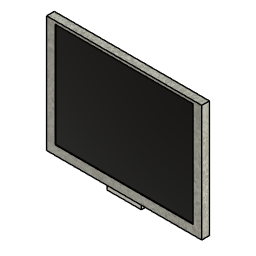
GNS 530 CAD v100 (Autodesk Fusion 360 archive; units mm, degrees)
design "GNS 530 5 inch Screen"
Autodesk Fusion 360 part; units mm, degrees
sketch "Sketch1" plane through (0, 0, 0) normal (0, 1, 0) x (1, 0, 0)
  line L0 (58.82, -44.225) -> (-58.82, -44.225)
  line L1 (-58.82, -44.225) -> (-58.82, 44.225)
  line L2 (-58.82, 44.225) -> (58.82, 44.225)
  line L3 (58.82, 44.225) -> (58.82, -44.225)
  line L4 (58.82, -44.225) -> (-58.82, 44.225) construction
  line L5 (-58.82, -44.225) -> (58.82, 44.225) construction
  line L6 (52.32, -41.925) -> (-52.32, -41.925)
  line L7 (-52.32, -41.925) -> (-52.32, 37.225)
  line L8 (-52.32, 37.225) -> (52.32, 37.225)
  line L9 (52.32, 37.225) -> (52.32, -41.925)
  line L10 (52.32, -41.925) -> (-52.32, 37.225) construction
  line L11 (-52.32, -41.925) -> (52.32, 37.225) construction
  point P0 (0, -2.35)
  dimension "d1" = 117.64
  dimension "d2" = 88.45
  dimension "d5" = 6.5
  dimension "d6" = 6.5
  dimension "d7" = 2.3
  dimension "d8" = 7
  constraint horizontal L0
  constraint perpendicular L0 L1
  constraint parallel L0 L2
  constraint parallel L1 L3
  constraint coincident L4 origin
  constraint coincident L5 origin
  constraint horizontal L6
  constraint perpendicular L6 L7
  constraint parallel L6 L8
  constraint parallel L7 L9
  constraint coincident L10 P0
  constraint coincident L11 P0
  measures "d1" distance of L1.end L2.end
  measures "d2" distance of L0.end L1.end
  measures "d5" distance of L3 L9
  measures "d6" distance of L1 L7
  measures "d7" distance of L0 L6
  measures "d8" distance of L2 L8
extrude "Extrude1" add sketch "Sketch1" along normal blind 5.85 contours L0 L1 L2 L3 | L6 L7 L8 L9 makes body 1
extrude "Extrude2" cut sketch "Sketch1" along normal blind 0.5 contours L6 L7 L8 L9 bodies 1
sketch "Sketch2" plane through (0, 0, -44.225) normal (0, 0, -1) x (1, 0, 0)
  line L0 (58.82, 0) -> (-58.82, 0)
  line L1 (-58.82, 0) -> (-58.82, -5.85)
  line L2 (-58.82, -5.85) -> (58.82, -5.85)
  line L3 (58.82, -5.85) -> (58.82, 0)
  line L4 (13, -5.85) -> (-13, -5.85)
  line L5 (-13, -5.85) -> (-13, 5.85)
  line L6 (-13, 5.85) -> (13, 5.85)
  line L7 (13, 5.85) -> (13, -5.85)
  line L8 (13, -5.85) -> (-13, 5.85) construction
  line L9 (-13, -5.85) -> (13, 5.85) construction
  dimension "d11" = 26
  constraint horizontal L4
  constraint perpendicular L4 L5
  constraint parallel L4 L6
  constraint parallel L5 L7
  constraint coincident L8 origin
  constraint coincident L9 origin
  measures "d11" distance of L5.end L6.end
extrude "Extrude3" add sketch "Sketch2" along normal blind 3 separate body contours L0 L2 L4 L5 L7 makes body 2
sketch "Sketch3" plane through (0, 5.85, 0) normal (0, 1, 0) x (-1, 0, 0)
  line L0 (-58.82, -44.225) -> (58.82, -44.225)
  line L1 (58.82, -44.225) -> (58.82, 44.225)
  line L2 (58.82, 44.225) -> (-58.82, 44.225)
  line L3 (-58.82, 44.225) -> (-58.82, -44.225)
  line L4 (57.94, 35.525) -> (55.29, 35.525)
  line L5 (55.29, 35.525) -> (55.29, 32.085)
  line L6 (55.29, 32.085) -> (57.94, 32.085)
  line L7 (57.94, 32.085) -> (57.94, 35.525)
  line L8 (55.29, -28.425) -> (57.94, -28.425)
  line L9 (57.94, -28.425) -> (57.94, -31.865)
  line L10 (57.94, -31.865) -> (55.29, -31.865)
  line L11 (55.29, -31.865) -> (55.29, -28.425)
  line L12 (-57.74, 35.525) -> (-52.39, 35.525)
  line L13 (-52.39, 35.525) -> (-52.39, 31.985)
  line L14 (-52.39, 31.985) -> (-57.74, 31.985)
  line L15 (-57.74, 31.985) -> (-57.74, 35.525)
  line L16 (-57.74, -31.865) -> (-52.39, -31.865)
  line L17 (-52.39, -31.865) -> (-52.39, -28.325)
  line L18 (-52.39, -28.325) -> (-57.74, -28.325)
  line L19 (-57.74, -28.325) -> (-57.74, -31.865)
  dimension "d14" = 0.88
  dimension "d15" = 2.65
  dimension "d16" = 3.44
  dimension "d17" = 8.7
  dimension "d18" = 12.36
  dimension "d19" = 5.35
  dimension "d20" = 3.54
  dimension "d22" = 1.08
  constraint horizontal L4
  constraint vertical L5
  constraint horizontal L6
  constraint vertical L7
  constraint horizontal L8
  constraint vertical L9
  constraint horizontal L10
  constraint vertical L11
  constraint equal L7 L9
  constraint equal L6 L8
  constraint collinear L7 L9
  constraint horizontal L12
  constraint vertical L13
  constraint horizontal L14
  constraint vertical L15
  constraint collinear L4 L12
  constraint horizontal L16
  constraint vertical L17
  constraint horizontal L18
  constraint vertical L19
  constraint equal L12 L18
  constraint equal L13 L17
  constraint collinear L15 L19
  constraint collinear L10 L16
  measures "d14" distance of L1 L7
  measures "d15" distance of L4.start L4.end
  measures "d16" distance of L4.end L5.end
  measures "d17" distance of L2 L4
  measures "d18" distance of L0 L10
  measures "d19" distance of L12.start L12.end
  measures "d20" distance of L12.start L14.end
  measures "d22" distance of L3 L15
extrude "Extrude4" cut sketch "Sketch3" against normal blind 3.7 contours L4 L5 L6 L7 | L8 L9 L10 L11 | L12 L13 L14 L15 | L16 L17 L18 L19 bodies 1

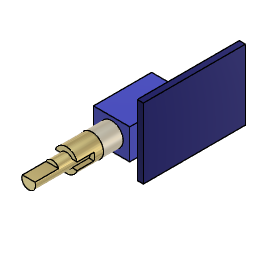
design "PropWashSim Dual Encoder (6mm screw, 6.5 loose)"
Autodesk Fusion 360 part; units mm, degrees
sketch "Profile" plane through (0, 0, 0) normal (0, 1, 0) x (1, 0, 0)
  line L0 (4.6, 3.85) -> (-4.6, 3.85)
  line L1 (-4.6, 3.85) -> (-4.6, -3.85)
  line L2 (-4.6, -3.85) -> (4.6, -3.85)
  line L3 (4.6, -3.85) -> (4.6, 3.85)
  line L4 (4.6, 3.85) -> (-4.6, -3.85) construction
  line L5 (-4.6, 3.85) -> (4.6, -3.85) construction
  circle A0 centre (0, 0) radius 2.925
  line L6 (2.235, -1.8869) -> (2.235, 1.8869)
  line L7 (0, 0) -> (0, 6.159) construction
  line L8 (-2.235, -1.8869) -> (-2.235, 1.8869)
  line L9 (-2.7664, -0.95) -> (2.7664, -0.95)
  line L10 (0, 0) -> (1.3963, 0) construction
  line L11 (-2.7664, 0.95) -> (2.7664, 0.95)
  dimension "d1" = 9.2
  dimension "d2" = 7.7
  dimension "d3" = 5.85
  dimension "d17" = 2.235
  dimension "d18" = 0.95
  constraint horizontal L0
  constraint perpendicular L0 L1
  constraint parallel L0 L2
  constraint parallel L1 L3
  constraint coincident L4 A0.centre
  constraint coincident L5 A0.centre
  constraint coincident A0.centre L7.start
  constraint coincident A0 L6.start
  constraint vertical L6
  constraint coincident A0 L6.end
  constraint vertical L7
  constraint symmetric L6.start L7 L8.start
  constraint symmetric L6.end L7 L8.end
  constraint coincident A0 L9.start
  constraint coincident A0 L9.end
  constraint horizontal L9
  constraint perpendicular L7 L10
  constraint symmetric L9.start L10 L11.start
  constraint symmetric L9.end L10 L11.end
  measures "d1" distance of L1.end L2.end
  measures "d2" distance of L0.end L1.end
  measures "d3" diameter of A0
  measures "d17" distance of A0.centre L6
  measures "d18" distance of A0.centre L9
extrude "Extrude1" add sketch "Profile" along normal blind 14.75 contours L0 L1 L2 L3 | A0 L6 L9 L11 | A0 L6 L11 | A0 L6 L9 | A0 L6 L8 L11 | L6 L8 L9 L11 | A0 L6 L8 L9 | A0 L8 L11 | A0 L8 L9 L11 | A0 L8 L9 makes body 1
extrude "Extrude2" add sketch "Profile" against normal blind 5 contours A0 L6 L9 L11 | A0 L6 L11 | A0 L6 L9 | A0 L6 L8 L11 | L6 L8 L9 L11 | A0 L6 L8 L9 | A0 L8 L11 | A0 L8 L9 L11 | A0 L8 L9 bodies 1
extrude "Extrude3" add sketch "Profile" against normal blind 6.5 from surface at -5 separate body contours A0 L6 L11 | A0 L6 L9 | A0 L6 L8 L11 | A0 L6 L8 L9 | A0 L8 L11 | A0 L8 L9 makes body 2 at (1.1749, -9.3333, -2.6787) makes body 3 at (-1.1749, -9.3333, 2.6787)
extrude "Extrude5" add sketch "Profile" against normal blind 2.25 from surface at -5 separate body contours A0 L6 L9 L11 | L6 L8 L9 L11 | A0 L8 L9 L11 makes body 4
combine "Combine1" operation add target body 3 tool bodies 4 2
cylinder "CylinderPrimitive1" add diameter 3.5 height 9.55 placed x (1, 0, 0) y (0, 0, 1) z (0, -1, 0) at (0, -11.5, 0) bodies 3
sketch "PCB" plane through (4.6, 0, 0) normal (1, 0, 0) x (0, 1, 0)
  line L0 (0, 3.85) -> (0, -3.85)
  line L1 (0, -3.85) -> (14.75, -3.85)
  line L2 (14.75, -3.85) -> (14.75, 3.85)
  line L3 (14.75, 3.85) -> (0, 3.85)
  line L4 (27.8, 8.9) -> (1.9, 8.9)
  line L5 (1.9, 8.9) -> (1.9, -8.9)
  line L6 (1.9, -8.9) -> (27.8, -8.9)
  line L7 (27.8, -8.9) -> (27.8, 8.9)
  line L8 (27.8, 8.9) -> (1.9, -8.9) construction
  line L9 (1.9, 8.9) -> (27.8, -8.9) construction
  point P0 (14.85, 0)
  dimension "d12" = 25.9
  dimension "d13" = 17.8
  dimension "d14" = 1.9
  constraint horizontal L4
  constraint perpendicular L4 L5
  constraint parallel L4 L6
  constraint parallel L5 L7
  constraint coincident L8 P0
  constraint coincident L9 P0
  constraint horizontal origin P0
  measures "d12" distance of L5.end L6.end
  measures "d13" distance of L4.end L5.end
  measures "d14" distance of origin L5
extrude "Extrude4" add sketch "PCB" along normal blind 1.55 separate body contours L1 L2 L3 L4 L5 L6 L7 | L1 L2 L3 L5 makes body 5
extrude "Extrude6" add 1 faces at (-0.4497, -11.5, 0.2434) along direction (0, 1, 0) up to surface (4.25 mm away) on bodies 3 bodies 3
sketch "Sketch4" plane through (0, -21.05, 0) normal (0, -1, 0) x (1, 0, 0)
  circle A0 centre (0, 0) radius 1.75
  line L0 (-1.6039, 0.7) -> (1.6039, 0.7)
  dimension "d25" = 2.45
  constraint coincident A0 L0.start
  constraint coincident A0 L0.end
  constraint horizontal L0
extrude "Extrude7" cut sketch "Sketch4" against normal blind 6 contours A0 L0 picked at (-0.2322, 1.2474) bodies 3
equation "d17 = ( 4.47 / 2 ) * 1 mm"
equation "d18 = ( 1.9 / 2 ) * 1 mm"

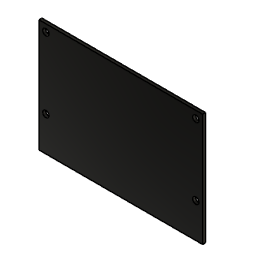
design "5  PCB Display Driver"
Autodesk Fusion 360 part; units mm, degrees
sketch "Sketch1" plane through (0, 0, 0) normal (0, 1, 0) x (1, 0, 0)
  line L0 (45, -31) -> (-45, -31)
  line L1 (-45, -31) -> (-45, 31)
  line L2 (-45, 31) -> (45, 31)
  line L3 (45, 31) -> (45, -31)
  line L4 (45, -31) -> (-45, 31) construction
  line L5 (-45, -31) -> (45, 31) construction
  line L6 (41.25, 12) -> (-41.25, 12) construction
  line L7 (-41.25, 12) -> (-41.25, -27) construction
  line L8 (-41.25, -27) -> (41.25, -27) construction
  line L9 (41.25, -27) -> (41.25, 12) construction
  line L10 (41.25, 12) -> (-41.25, -27) construction
  line L11 (-41.25, 12) -> (41.25, -27) construction
  circle A0 centre (-41.25, -27) radius 1.75
  circle A1 centre (41.25, -27) radius 1.75
  circle A2 centre (-41.25, 12) radius 1.75
  circle A3 centre (41.25, 12) radius 1.75
  line L12 (25, 31) -> (10, 31)
  line L13 (10, 31) -> (10, 19)
  line L14 (10, 19) -> (25, 19)
  line L15 (25, 19) -> (25, 31)
  point P0 (0, -7.5)
  dimension "d1" = 90
  dimension "d2" = 62
  dimension "d3" = 3.5
  dimension "d4" = 82.5
  dimension "d5" = 39
  dimension "d6" = 4
  dimension "d9" = 15
  dimension "d10" = 20
  dimension "d11" = 12
  constraint horizontal L0
  constraint perpendicular L0 L1
  constraint parallel L0 L2
  constraint parallel L1 L3
  constraint coincident L4 origin
  constraint coincident L5 origin
  constraint horizontal L6
  constraint perpendicular L6 L7
  constraint parallel L6 L8
  constraint parallel L7 L9
  constraint coincident L10 P0
  constraint coincident L11 P0
  constraint coincident L7.end L8.start
  constraint coincident L8.end L9.start
  constraint coincident L6.end L7.start
  constraint coincident L6.start L9.end
  constraint equal A0 A1
  constraint equal A0 A2
  constraint equal A1 A3
  constraint vertical origin P0
  constraint horizontal L12
  constraint vertical L13
  constraint horizontal L14
  constraint vertical L15
  constraint coincident L2 L12.start
  measures "d1" distance of L1.end L2.end
  measures "d2" distance of L0.end L1.end
  measures "d3" diameter of A1
  measures "d4" distance of L7.end L8.end
  measures "d5" distance of L6.start L8.end
  measures "d6" distance of L0 L8
  measures "d9" distance of L12.start L12.end
  measures "d10" distance of L3 L15
  measures "d11" distance of L12.end L13.end
extrude "Extrude1" add sketch "Sketch1" along normal blind 1.6
extrude "Extrude2" add sketch "Sketch1" along normal blind 7.87 contours L2 L12 L13 L14 L15
